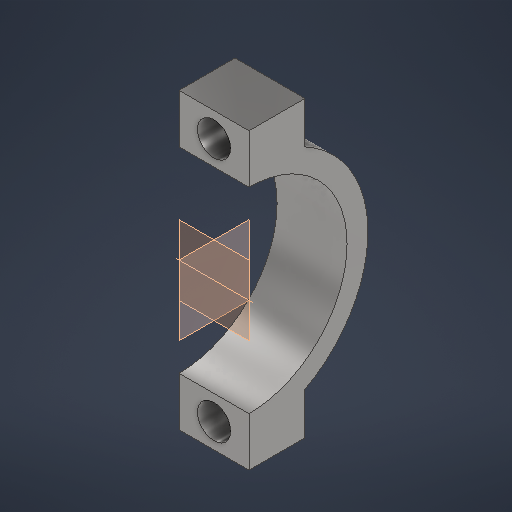
# Autodesk Inventor part: Rod_Cap
Saved by Autodesk Inventor 2027.1 (Build 311270010, 270A)
## iProperties
Created: 2026-10-17
Part Number: Rod_Cap
Material: Steel, Alloy
Document SubType Name: Modeling
Designer: kashyap
Density: 7.73 g/cm^3
Appearance: Semi-Polished
Mass: 118.434 g
Surface Area: 73.4035 cm^2
Volume: 15.3214 cm^3
Material_Status: Assumed for this reconstruction
Author: kashyap
Autodesk Inventor part; units mm, degrees
derived "V6_Engine_Master.ipt"
ref_plane "Rod_Mid_Plane" through (0, 0, 0) normal (1, 0, 0) x (0, 1, 0)
ref_plane "Cap_Split_Plane" through (0, 0, 0) normal (0, 0, 1) x (1, 0, 0)
sketch "SK_Cap_Eye" plane through (0, 0, 0) normal (1, 0, 0) x (0, 1, 0)
  circle A0 centre (0, 0) radius 34
  dimension "d21" = 68
  constraints: 1 centre point
  measures "d21" diameter of A0
extrude "Cap_Eye" add sketch "SK_Cap_Eye" along normal mid plane 20
sketch "SK_Cap_Bosses" plane through (0, 0, 0) normal (1, 0, 0) x (0, 1, 0)
  line L0 (0, 3.2) -> (0, -19.2) construction
  line L1 (-58.8, 0) -> (58.8, 0) construction
  line L2 (-42, 0) -> (42, 0)
  line L3 (42, 0) -> (42, -16)
  line L4 (42, -16) -> (-42, -16)
  line L5 (-42, -16) -> (-42, 0)
  dimension "d24" = 42
  dimension "d25" = 42
  dimension "d26" = 16
  constraints: 8 end point, 2 parallel, 1 collinear, 1 horizontal, 1 perpendicular
  measures "d24" distance between parallel lines of L5 L0
  measures "d25" distance between parallel lines of L3 L0
  measures "d26" distance between parallel lines of L4 L1
extrude "Cap_Bosses" add sketch "SK_Cap_Bosses" along normal mid plane 20
sketch "SK_Split_Cut" plane through (0, 0, 0) normal (1, 0, 0) x (0, 1, 0)
  line L0 (-60, 0) -> (60, 0)
  line L1 (60, 0) -> (60, 60)
  line L2 (60, 60) -> (-60, 60)
  line L3 (-60, 60) -> (-60, 0)
  constraints: 8 end point, 2 parallel, 1 horizontal, 1 perpendicular
extrude "Split_Cut" cut sketch "SK_Split_Cut" along normal mid plane 22
sketch "SK_Cap_Bore" plane through (0, 0, 0) normal (1, 0, 0) x (0, 1, 0)
  circle A0 centre (0, 0) radius 28.028
  dimension "d31" = 56.056
  constraints: 1 centre point
  measures "d31" diameter of A0
extrude "Cap_Bore" cut sketch "SK_Cap_Bore" along normal mid plane 22
sketch "SK_Cap_Bolt_Holes" plane through (0, 0, 0) normal (0, 0, 1) x (1, 0, 0)
  line L0 (-6.65, 0) -> (6.65, 0) construction
  line L1 (0, 55.65) -> (0, -55.65) construction
  circle A0 centre (0, 35) radius 4.75
  circle A1 centre (0, -35) radius 4.75
  dimension "d34" = 9.5
  dimension "d35" = 35
  dimension "d36" = 9.5
  dimension "d37" = 35
  constraints: 2 centre point, 2 point on line
  measures "d34" diameter of A0
  measures "d35" distance from line of L0 A0.centre
  measures "d36" diameter of A1
  measures "d37" distance from line of L0 A1.centre
extrude "Cap_Bolt_Holes" cut sketch "SK_Cap_Bolt_Holes" against normal blind 16
equation "\"d21\" = Rod_BigEnd_OD"
equation "\"d22\" = Rod_BigEnd_Width"
equation "\"d24\" = Rod_Boss_Half_Width"
equation "\"d25\" = Rod_Boss_Half_Width"
equation "\"d26\" = Rod_Cap_Boss_Depth"
equation "\"d27\" = Rod_BigEnd_Width"
equation "\"d31\" = Rod_BigEnd_Bore"
equation "\"d34\" = Rod_Bolt_Hole_Dia"
equation "\"d35\" = Rod_Bolt_Y"
equation "\"d36\" = Rod_Bolt_Hole_Dia"
equation "\"d37\" = Rod_Bolt_Y"
equation "\"d38\" = Rod_Cap_Boss_Depth"
equation "\"Rod_BigEnd_OD\" = 68"
equation "\"Rod_BigEnd_Width\" = 20"
equation "\"Rod_Boss_Half_Width\" = 42"
equation "\"Rod_Cap_Boss_Depth\" = 16"
equation "\"Rod_BigEnd_Bore\" = 56.056"
equation "\"Rod_Bolt_Hole_Dia\" = 9.5"
equation "\"Rod_Bolt_Y\" = 35"
body "Solid1"
